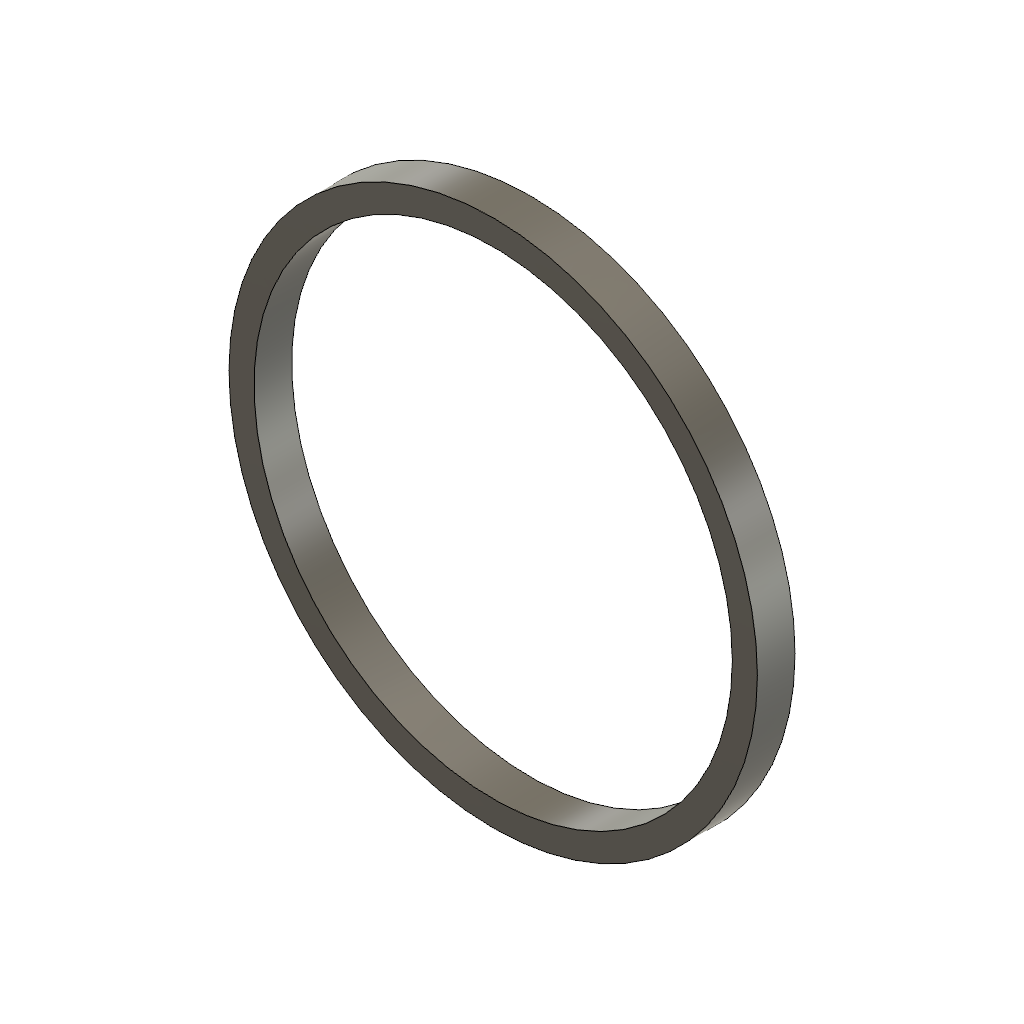
closed_circle (Autodesk Fusion 360 design; units mm, degrees)
part number: 2026-10-20-22-05-58-512
Autodesk Fusion 360 part; units mm, degrees
sketch "SweepSection" plane through (0, 0, 0) normal (1, 0, 0) x (0, 0, -1)
  line L0 (-3, -2) -> (3, -2)
  line L1 (3, -2) -> (3, 2)
  line L2 (3, 2) -> (-3, 2)
  line L3 (-3, 2) -> (-3, -2)
sketch "SweepPath" plane through (0, 0, 0) normal (0, 0, 1) x (1, 0, 0)
  circle A0 centre (0, 40) radius 40
sweep "ProbeSweep" add profiles "SweepSection" path "SweepPath" along A0 section 1
